push_rod_attache_v1 (Autodesk Fusion 360 design; units mm, degrees)
Autodesk Fusion 360 part; units mm, degrees
sketch "Sketch1" plane through (0, 0, 0) normal (1, 0, 0) x (0, 1, 0)
  line L0 (30, -9) -> (30, 9)
  line L1 (0, -9) -> (0, 9)
  line L2 (30, 9) -> (36.4452, 15.5161)
  circle A0 centre (40, 12) radius 5
  circle A1 centre (40, 12) radius 1.65
  line L3 (50, 9) -> (50, -9)
  circle A2 centre (0, 0) radius 9
  line L4 (40, -9) -> (40, -12)
  line L5 (30, -9) -> (36.4452, -15.5161)
  line L6 (0, 9) -> (50, 9)
  line L7 (50, -9) -> (43.5548, -15.5161)
  circle A3 centre (0, 0) radius 4.1
  line L8 (50, 9) -> (50, -9)
  line L9 (50, 9) -> (43.5548, 15.5161)
  circle A4 centre (40, -12) radius 1.65
  line L10 (30, 9) -> (50, 9)
  circle A5 centre (40, -12) radius 5
  line L11 (50, -9) -> (30, -9)
  line L12 (50, -9) -> (0, -9)
  line L13 (40, 9) -> (40, 12)
  dimension "d1" = 8.2
  dimension "d2" = 18
  dimension "d3" = 50
  dimension "d4" = 3.3
  dimension "d5" = 20
  dimension "d6" = 3
  dimension "d7" = 3
  dimension "d8" = 3.3
  dimension "d9" = 10
  dimension "d10" = 10
  constraint coincident A2.centre A3.centre
  constraint concentric A2 A3
  constraint horizontal L6
  constraint vertical L8
  constraint horizontal L12
  constraint vertical L1
  constraint coincident L1.end A2
  constraint coincident L1.start A2
  constraint tangent A2 L12
  constraint horizontal L11
  constraint vertical L0
  constraint horizontal L10
  constraint vertical L3
  constraint midpoint L13.start L10
  constraint coincident A0.centre A1.centre
  constraint midpoint L4.start L11
  constraint perpendicular L4 L12
  constraint perpendicular L6 L13
  constraint coincident L4.end A4.centre
  constraint concentric A4 A5
  constraint collinear L6 L10
  constraint coincident L2.end A0
  constraint tangent L2 A0
  constraint coincident L9.end A0
  constraint tangent A0 L9
  constraint coincident L7.end A5
  constraint tangent L7 A5
  constraint coincident L5.end A5
  constraint tangent L5 A5
  measures "d1" diameter of A3
  measures "d2" diameter of A2
  measures "d3" distance of L1.end L3.start
  measures "d4" diameter of A1
  measures "d5" distance of L3.end L0.start
  measures "d6" distance of L4.start L4.end
  measures "d7" vertical distance of L13.start A0.centre
  measures "d8" diameter of A4
  measures "d9" diameter of A5
  measures "d10" diameter of A0
extrude "Extrude1" add sketch "Sketch1" along normal blind 4.5 contours L0 A2 L6 L12 | L1 A2 A3 | L1 A2 A3
extrude "Extrude2" add sketch "Sketch1" along normal blind 8 contours L5 A5 L11 L12 | L0 A0 L3 L6 L8 L10 A5 L11 L12 | L2 A0 L6 L10 | A5 L11 L12 | A5 L11 L12 | A0 L6 L10 | A0 L6 L10 | L7 A5 L11 L12 | A0 L6 L9 L10
sketch "Sketch2" plane through (0, 50, 0) normal (0, 1, 0) x (-1, 0, 0)
  line L0 (0, -9) -> (0, 9)
  line L1 (0, 9) -> (-8, 9)
  line L2 (-8, 9) -> (-8, -9)
  line L3 (-8, -9) -> (0, -9)
  circle A0 centre (-8.8, 0) radius 7
  circle A1 centre (-8.8, 0) radius 6
  line L4 (0, 9) -> (0, -9)
  dimension "d15" = 14
  dimension "d16" = 12
  dimension "d17" = 8.8
  constraint concentric A0 A1
  measures "d15" diameter of A0
  measures "d16" diameter of A1
  measures "d17" distance of A0.centre L4
extrude "Extrude3" cut sketch "Sketch2" against normal blind 20 contours L2 A0 A1 | L2 A1 picked at (-7.6664, -6.555) picked at (-7.1961, 1.6893)
chamfer "Chamfer1" distance 3.5 angle 45 2 edges at (4.5, 30, 7.2618) (4.5, 30, -7.2618) tangent chain off
fillet "Fillet1" radius 25 2 edges at (4, 30, -9) (4, 30, 9)
